Autodesk Inventor part; units mm, degrees
(part 2 of 2)
  spline S115 degree 3 poles (8.085, 6.6965) (8.085, 6.6966) (8.0755, 6.8111) (8.1685, 6.9061) (8.2142, 6.9788) knots 0.189655 0.189655 0.189655 0.189655 0.189655 0.206897 0.206897 0.206897 0.206897
  line L349 (8.085, 6.6965) -> (8.0755, 6.8111) construction
  line L350 (8.0755, 6.8111) -> (8.1685, 6.9061) construction
  line L351 (8.1685, 6.9061) -> (8.2142, 6.9788) construction
  spline S116 degree 3 poles (8.2142, 6.9788) (8.2143, 6.979) (8.3545, 7.2023) (8.3469, 7.2941) (8.4331, 7.5539) knots 0.206897 0.206897 0.206897 0.206897 0.206897 0.224138 0.224138 0.224138 0.224138
  line L352 (8.2142, 6.9788) -> (8.3545, 7.2023) construction
  line L353 (8.3545, 7.2023) -> (8.3469, 7.2941) construction
  line L354 (8.3469, 7.2941) -> (8.4331, 7.5539) construction
  spline S117 degree 3 poles (8.4331, 7.5539) (8.4331, 7.5541) (8.5076, 7.7786) (8.5783, 7.9124) (8.624, 8.1718) knots 0.224138 0.224138 0.224138 0.224138 0.224138 0.241379 0.241379 0.241379 0.241379
  line L355 (8.4331, 7.5539) -> (8.5076, 7.7786) construction
  line L356 (8.5076, 7.7786) -> (8.5783, 7.9124) construction
  line L357 (8.5783, 7.9124) -> (8.624, 8.1718) construction
  spline S118 degree 3 poles (8.624, 8.1718) (8.624, 8.172) (8.6663, 8.4124) (8.6795, 8.6592) (8.7001, 8.9071) knots 0.241379 0.241379 0.241379 0.241379 0.241379 0.258621 0.258621 0.258621 0.258621
  line L358 (8.624, 8.1718) -> (8.6663, 8.4124) construction
  line L359 (8.6663, 8.4124) -> (8.6795, 8.6592) construction
  line L360 (8.6795, 8.6592) -> (8.7001, 8.9071) construction
  spline S119 degree 3 poles (8.7001, 8.9071) (8.7001, 8.9073) (8.7102, 9.0279) (8.7321, 9.1622) (8.729, 9.2829) knots 0.258621 0.258621 0.258621 0.258621 0.258621 0.275862 0.275862 0.275862 0.275862
  line L361 (8.7001, 8.9071) -> (8.7102, 9.0279) construction
  line L362 (8.7102, 9.0279) -> (8.7321, 9.1622) construction
  line L363 (8.7321, 9.1622) -> (8.729, 9.2829) construction
  spline S120 degree 3 poles (8.729, 9.2829) (8.729, 9.283) (8.7263, 9.3865) (8.6763, 9.5788) (8.6969, 9.6501) knots 0.275862 0.275862 0.275862 0.275862 0.275862 0.293103 0.293103 0.293103 0.293103
  line L364 (8.729, 9.2829) -> (8.7263, 9.3865) construction
  line L365 (8.7263, 9.3865) -> (8.6763, 9.5788) construction
  line L366 (8.6763, 9.5788) -> (8.6969, 9.6501) construction
  spline S121 degree 3 poles (8.6969, 9.6501) (8.697, 9.6501) (8.8157, 9.6248) (8.819, 9.477) (8.9266, 9.3796) knots 0.293103 0.293103 0.293103 0.293103 0.293103 0.310345 0.310345 0.310345 0.310345
  line L367 (8.6969, 9.6501) -> (8.8157, 9.6248) construction
  line L368 (8.8157, 9.6248) -> (8.819, 9.477) construction
  line L369 (8.819, 9.477) -> (8.9266, 9.3796) construction
  spline S122 degree 3 poles (8.9266, 9.3796) (8.9268, 9.3797) (9.0711, 9.4527) (8.9677, 9.5952) (8.9205, 9.7051) knots 0.310345 0.310345 0.310345 0.310345 0.310345 0.327586 0.327586 0.327586 0.327586
  line L370 (8.9266, 9.3796) -> (9.0711, 9.4527) construction
  line L371 (9.0711, 9.4527) -> (8.9677, 9.5952) construction
  line L372 (8.9677, 9.5952) -> (8.9205, 9.7051) construction
  spline S123 degree 3 poles (8.9205, 9.7051) (8.9204, 9.7053) (8.8408, 9.891) (8.8788, 9.9473) (8.9212, 10.1294) knots 0.327586 0.327586 0.327586 0.327586 0.327586 0.344828 0.344828 0.344828 0.344828
  line L373 (8.9205, 9.7051) -> (8.8408, 9.891) construction
  line L374 (8.8408, 9.891) -> (8.8788, 9.9473) construction
  line L375 (8.8788, 9.9473) -> (8.9212, 10.1294) construction
  spline S124 degree 3 poles (8.9212, 10.1294) (8.9213, 10.1298) (9.0126, 10.5216) (8.7808, 10.9359) (8.5155, 11.2056) knots 0.344828 0.344828 0.344828 0.344828 0.344828 0.362069 0.362069 0.362069 0.362069
  line L376 (8.9212, 10.1294) -> (9.0126, 10.5216) construction
  line L377 (9.0126, 10.5216) -> (8.7808, 10.9359) construction
  line L378 (8.7808, 10.9359) -> (8.5155, 11.2056) construction
  spline S125 degree 3 poles (8.5155, 11.2056) (8.5153, 11.2057) (8.3918, 11.3312) (8.3839, 11.3395) (8.2897, 11.4877) knots 0.362069 0.362069 0.362069 0.362069 0.362069 0.37931 0.37931 0.37931 0.37931
  line L379 (8.5155, 11.2056) -> (8.3918, 11.3312) construction
  line L380 (8.3918, 11.3312) -> (8.3839, 11.3395) construction
  line L381 (8.3839, 11.3395) -> (8.2897, 11.4877) construction
  spline S126 degree 3 poles (8.2897, 11.4877) (8.2894, 11.488) (8.06, 11.8487) (8.0055, 11.7291) (7.6324, 11.6247) knots 0.37931 0.37931 0.37931 0.37931 0.37931 0.396552 0.396552 0.396552 0.396552
  line L382 (8.2897, 11.4877) -> (8.06, 11.8487) construction
  line L383 (8.06, 11.8487) -> (8.0055, 11.7291) construction
  line L384 (8.0055, 11.7291) -> (7.6324, 11.6247) construction
  spline S127 degree 3 poles (7.6324, 11.6247) (7.6324, 11.6247) (7.6491, 11.6371) (7.7644, 11.7585) (7.7775, 11.7819) knots 0.396552 0.396552 0.396552 0.396552 0.396552 0.413793 0.413793 0.413793 0.413793
  line L385 (7.6324, 11.6247) -> (7.6491, 11.6371) construction
  line L386 (7.6491, 11.6371) -> (7.7644, 11.7585) construction
  line L387 (7.7644, 11.7585) -> (7.7775, 11.7819) construction
  spline S128 degree 3 poles (7.7775, 11.7819) (7.7775, 11.7819) (7.8236, 11.8645) (7.7746, 11.9476) (7.7568, 12.0241) knots 0.413793 0.413793 0.413793 0.413793 0.413793 0.431034 0.431034 0.431034 0.431034
  line L388 (7.7775, 11.7819) -> (7.8236, 11.8645) construction
  line L389 (7.8236, 11.8645) -> (7.7746, 11.9476) construction
  line L390 (7.7746, 11.9476) -> (7.7568, 12.0241) construction
  spline S129 degree 3 poles (7.7568, 12.0241) (7.7571, 12.024) (8.0858, 11.859) (8.3087, 11.8206) (8.549, 12.0896) knots 0.431034 0.431034 0.431034 0.431034 0.431034 0.448276 0.448276 0.448276 0.448276
  line L391 (7.7568, 12.0241) -> (8.0858, 11.859) construction
  line L392 (8.0858, 11.859) -> (8.3087, 11.8206) construction
  line L393 (8.3087, 11.8206) -> (8.549, 12.0896) construction
  spline S130 degree 3 poles (8.549, 12.0896) (8.5492, 12.0898) (8.7512, 12.316) (8.8468, 12.4373) (8.9463, 12.8199) knots 0.448276 0.448276 0.448276 0.448276 0.448276 0.465517 0.465517 0.465517 0.465517
  line L394 (8.549, 12.0896) -> (8.7512, 12.316) construction
  line L395 (8.7512, 12.316) -> (8.8468, 12.4373) construction
  line L396 (8.8468, 12.4373) -> (8.9463, 12.8199) construction
  spline S131 degree 3 poles (8.9463, 12.8199) (8.9464, 12.8205) (9.0844, 13.3511) (9.2219, 14.254) (9.1072, 14.8125) knots 0.465517 0.465517 0.465517 0.465517 0.465517 0.482759 0.482759 0.482759 0.482759
  line L397 (8.9463, 12.8199) -> (9.0844, 13.3511) construction
  line L398 (9.0844, 13.3511) -> (9.2219, 14.254) construction
  line L399 (9.2219, 14.254) -> (9.1072, 14.8125) construction
  spline S132 degree 3 poles (9.1072, 14.8125) (9.1071, 14.8133) (8.9494, 15.581) (8.9114, 15.3471) (8.6266, 15.9994) knots 0.482759 0.482759 0.482759 0.482759 0.482759 0.5 0.5 0.5 0.5
  line L400 (9.1072, 14.8125) -> (8.9494, 15.581) construction
  line L401 (8.9494, 15.581) -> (8.9114, 15.3471) construction
  line L402 (8.9114, 15.3471) -> (8.6266, 15.9994) construction
  spline S133 degree 3 poles (8.6266, 15.9994) (8.6266, 15.9996) (8.5453, 16.1857) (8.0147, 16.2744) (7.8202, 16.319) knots 0.5 0.5 0.5 0.5 0.5 0.517241 0.517241 0.517241 0.517241
  line L403 (8.6266, 15.9994) -> (8.5453, 16.1857) construction
  line L404 (8.5453, 16.1857) -> (8.0147, 16.2744) construction
  line L405 (8.0147, 16.2744) -> (7.8202, 16.319) construction
  spline S134 degree 3 poles (7.8202, 16.319) (7.8197, 16.3191) (7.3838, 16.419) (7.4051, 16.0463) (7.2832, 15.7677) knots 0.517241 0.517241 0.517241 0.517241 0.517241 0.534483 0.534483 0.534483 0.534483
  line L406 (7.8202, 16.319) -> (7.3838, 16.419) construction
  line L407 (7.3838, 16.419) -> (7.4051, 16.0463) construction
  line L408 (7.4051, 16.0463) -> (7.2832, 15.7677) construction
  spline S135 degree 3 poles (7.2832, 15.7677) (7.2831, 15.7676) (7.228, 15.6417) (7.1184, 15.5346) (7.0933, 15.388) knots 0.534483 0.534483 0.534483 0.534483 0.534483 0.551724 0.551724 0.551724 0.551724
  line L409 (7.2832, 15.7677) -> (7.228, 15.6417) construction
  line L410 (7.228, 15.6417) -> (7.1184, 15.5346) construction
  line L411 (7.1184, 15.5346) -> (7.0933, 15.388) construction
  spline S136 degree 3 poles (7.0933, 15.388) (7.0933, 15.3879) (7.0679, 15.2397) (7.1046, 15.0222) (7.1143, 14.8711) knots 0.551724 0.551724 0.551724 0.551724 0.551724 0.568966 0.568966 0.568966 0.568966
  line L412 (7.0933, 15.388) -> (7.0679, 15.2397) construction
  line L413 (7.0679, 15.2397) -> (7.1046, 15.0222) construction
  line L414 (7.1046, 15.0222) -> (7.1143, 14.8711) construction
  spline S137 degree 3 poles (7.1143, 14.8711) (7.1143, 14.8709) (7.1285, 14.6518) (7.0596, 14.6036) (7.0137, 14.4186) knots 0.568966 0.568966 0.568966 0.568966 0.568966 0.586207 0.586207 0.586207 0.586207
  line L415 (7.1143, 14.8711) -> (7.1285, 14.6518) construction
  line L416 (7.1285, 14.6518) -> (7.0596, 14.6036) construction
  line L417 (7.0596, 14.6036) -> (7.0137, 14.4186) construction
  spline S138 degree 3 poles (7.0137, 14.4186) (7.0137, 14.4184) (6.9778, 14.2738) (6.9857, 13.9978) (6.9579, 13.9186) knots 0.586207 0.586207 0.586207 0.586207 0.586207 0.603448 0.603448 0.603448 0.603448
  line L418 (7.0137, 14.4186) -> (6.9778, 14.2738) construction
  line L419 (6.9778, 14.2738) -> (6.9857, 13.9978) construction
  line L420 (6.9857, 13.9978) -> (6.9579, 13.9186) construction
  spline S139 degree 3 poles (6.9579, 13.9186) (6.9579, 13.9186) (6.9279, 13.8333) (6.7142, 13.7453) (6.6278, 13.6772) knots 0.603448 0.603448 0.603448 0.603448 0.603448 0.62069 0.62069 0.62069 0.62069
  line L421 (6.9579, 13.9186) -> (6.9279, 13.8333) construction
  line L422 (6.9279, 13.8333) -> (6.7142, 13.7453) construction
  line L423 (6.7142, 13.7453) -> (6.6278, 13.6772) construction
  spline S140 degree 3 poles (6.6278, 13.6772) (6.6275, 13.677) (6.357, 13.4638) (6.3021, 13.3051) (5.9997, 13.1943) knots 0.62069 0.62069 0.62069 0.62069 0.62069 0.637931 0.637931 0.637931 0.637931
  line L424 (6.6278, 13.6772) -> (6.357, 13.4638) construction
  line L425 (6.357, 13.4638) -> (6.3021, 13.3051) construction
  line L426 (6.3021, 13.3051) -> (5.9997, 13.1943) construction
  spline S141 degree 3 poles (5.9997, 13.1943) (5.9994, 13.1942) (5.6348, 13.0606) (5.3959, 13.3366) (5.221, 13.4672) knots 0.637931 0.637931 0.637931 0.637931 0.637931 0.655172 0.655172 0.655172 0.655172
  line L427 (5.9997, 13.1943) -> (5.6348, 13.0606) construction
  line L428 (5.6348, 13.0606) -> (5.3959, 13.3366) construction
  line L429 (5.3959, 13.3366) -> (5.221, 13.4672) construction
  spline S142 degree 3 poles (5.221, 13.4672) (5.2206, 13.4675) (4.7972, 13.7836) (4.7334, 13.716) (4.4825, 13.552) knots 0.655172 0.655172 0.655172 0.655172 0.655172 0.672414 0.672414 0.672414 0.672414
  line L430 (5.221, 13.4672) -> (4.7972, 13.7836) construction
  line L431 (4.7972, 13.7836) -> (4.7334, 13.716) construction
  line L432 (4.7334, 13.716) -> (4.4825, 13.552) construction
  spline S143 degree 3 poles (4.4825, 13.552) (4.4824, 13.5519) (4.3251, 13.4491) (4.2622, 13.4755) (4.2786, 13.2069) knots 0.672414 0.672414 0.672414 0.672414 0.672414 0.689655 0.689655 0.689655 0.689655
  line L433 (4.4825, 13.552) -> (4.3251, 13.4491) construction
  line L434 (4.3251, 13.4491) -> (4.2622, 13.4755) construction
  line L435 (4.2622, 13.4755) -> (4.2786, 13.2069) construction
  spline S144 degree 3 poles (4.2786, 13.2069) (4.2786, 13.2067) (4.2897, 13.0241) (4.3834, 12.9269) (4.2992, 12.7362) knots 0.689655 0.689655 0.689655 0.689655 0.689655 0.706897 0.706897 0.706897 0.706897
  line L436 (4.2786, 13.2069) -> (4.2897, 13.0241) construction
  line L437 (4.2897, 13.0241) -> (4.3834, 12.9269) construction
  line L438 (4.3834, 12.9269) -> (4.2992, 12.7362) construction
  spline S145 degree 3 poles (4.2992, 12.7362) (4.2991, 12.736) (4.1856, 12.479) (4.0388, 12.1321) (4.2245, 11.8355) knots 0.706897 0.706897 0.706897 0.706897 0.706897 0.724138 0.724138 0.724138 0.724138
  line L439 (4.2992, 12.7362) -> (4.1856, 12.479) construction
  line L440 (4.1856, 12.479) -> (4.0388, 12.1321) construction
  line L441 (4.0388, 12.1321) -> (4.2245, 11.8355) construction
  spline S146 degree 3 poles (4.2245, 11.8355) (4.2245, 11.8354) (4.2873, 11.7351) (4.4143, 11.6294) (4.4987, 11.5541) knots 0.724138 0.724138 0.724138 0.724138 0.724138 0.741379 0.741379 0.741379 0.741379
  line L442 (4.2245, 11.8355) -> (4.2873, 11.7351) construction
  line L443 (4.2873, 11.7351) -> (4.4143, 11.6294) construction
  line L444 (4.4143, 11.6294) -> (4.4987, 11.5541) construction
  spline S147 degree 3 poles (4.4987, 11.5541) (4.4987, 11.5541) (4.541, 11.5164) (4.6082, 11.4653) (4.661, 11.4309) knots 0.741379 0.741379 0.741379 0.741379 0.741379 0.758621 0.758621 0.758621 0.758621
  line L445 (4.4987, 11.5541) -> (4.541, 11.5164) construction
  line L446 (4.541, 11.5164) -> (4.6082, 11.4653) construction
  line L447 (4.6082, 11.4653) -> (4.661, 11.4309) construction
  spline S148 degree 3 poles (4.661, 11.4309) (4.6611, 11.4308) (4.7908, 11.3461) (4.8176, 11.3664) (4.8049, 11.31) knots 0.758621 0.758621 0.758621 0.758621 0.758621 0.775862 0.775862 0.775862 0.775862
  line L448 (4.661, 11.4309) -> (4.7908, 11.3461) construction
  line L449 (4.7908, 11.3461) -> (4.8176, 11.3664) construction
  line L450 (4.8176, 11.3664) -> (4.8049, 11.31) construction
  spline S149 degree 3 poles (4.8049, 11.31) (4.8049, 11.31) (4.8017, 11.3093) (4.7933, 11.3094) (4.7952, 11.3096) knots 0.775862 0.775862 0.775862 0.775862 0.775862 0.793103 0.793103 0.793103 0.793103
  line L451 (4.8049, 11.31) -> (4.8017, 11.3093) construction
  line L452 (4.8017, 11.3093) -> (4.7933, 11.3094) construction
  line L453 (4.7933, 11.3094) -> (4.7952, 11.3096) construction
  line L454 (4.7952, 11.3096) -> (4.7557, 11.3178)
  spline S150 degree 3 poles (4.7557, 11.3178) (4.7554, 11.318) (4.4638, 11.4421) (4.1528, 11.8927) (3.9604, 11.9522) knots 0.810345 0.810345 0.810345 0.810345 0.810345 0.827586 0.827586 0.827586 0.827586
  line L455 (4.7557, 11.3178) -> (4.4638, 11.4421) construction
  line L456 (4.4638, 11.4421) -> (4.1528, 11.8927) construction
  line L457 (4.1528, 11.8927) -> (3.9604, 11.9522) construction
  spline S151 degree 3 poles (3.9604, 11.9522) (3.96, 11.9523) (3.59, 12.0667) (3.4363, 11.3591) (3.4025, 11.0291) knots 0.827586 0.827586 0.827586 0.827586 0.827586 0.844828 0.844828 0.844828 0.844828
  line L458 (3.9604, 11.9522) -> (3.59, 12.0667) construction
  line L459 (3.59, 12.0667) -> (3.4363, 11.3591) construction
  line L460 (3.4363, 11.3591) -> (3.4025, 11.0291) construction
  spline S152 degree 3 poles (3.4025, 11.0291) (3.4025, 11.0283) (3.3226, 10.2465) (3.593, 9.2162) (3.8261, 8.468) knots 0.844828 0.844828 0.844828 0.844828 0.844828 0.862069 0.862069 0.862069 0.862069
  line L461 (3.4025, 11.0291) -> (3.3226, 10.2465) construction
  line L462 (3.3226, 10.2465) -> (3.593, 9.2162) construction
  line L463 (3.593, 9.2162) -> (3.8261, 8.468) construction
  spline S153 degree 3 poles (3.8261, 8.468) (3.8263, 8.4672) (4.081, 7.6498) (4.3337, 6.9842) (4.7794, 6.4056) knots 0.862069 0.862069 0.862069 0.862069 0.862069 0.87931 0.87931 0.87931 0.87931
  line L464 (3.8261, 8.468) -> (4.081, 7.6498) construction
  line L465 (4.081, 7.6498) -> (4.3337, 6.9842) construction
  line L466 (4.3337, 6.9842) -> (4.7794, 6.4056) construction
  spline S154 degree 3 poles (4.7794, 6.4056) (4.7797, 6.4053) (5.0066, 6.1106) (5.2537, 5.8563) (5.7594, 6.1164) knots 0.87931 0.87931 0.87931 0.87931 0.87931 0.896552 0.896552 0.896552 0.896552
  line L467 (4.7794, 6.4056) -> (5.0066, 6.1106) construction
  line L468 (5.0066, 6.1106) -> (5.2537, 5.8563) construction
  line L469 (5.2537, 5.8563) -> (5.7594, 6.1164) construction
  spline S155 degree 3 poles (5.7594, 6.1164) (5.7596, 6.1164) (5.9091, 6.1933) (6.2195, 6.3788) (6.324, 6.4879) knots 0.896552 0.896552 0.896552 0.896552 0.896552 0.913793 0.913793 0.913793 0.913793
  line L470 (5.7594, 6.1164) -> (5.9091, 6.1933) construction
  line L471 (5.9091, 6.1933) -> (6.2195, 6.3788) construction
  line L472 (6.2195, 6.3788) -> (6.324, 6.4879) construction
  spline S156 degree 3 poles (6.324, 6.4879) (6.3241, 6.488) (6.3604, 6.526) (6.382, 6.5485) (6.4177, 6.5851) knots 0.913793 0.913793 0.913793 0.913793 0.913793 0.931034 0.931034 0.931034 0.931034
  line L473 (6.324, 6.4879) -> (6.3604, 6.526) construction
  line L474 (6.3604, 6.526) -> (6.382, 6.5485) construction
  line L475 (6.382, 6.5485) -> (6.4177, 6.5851) construction
  spline S157 degree 3 poles (6.4177, 6.5851) (6.4177, 6.5851) (6.4603, 6.6287) (6.4739, 6.6423) (6.5067, 6.6866) knots 0.931034 0.931034 0.931034 0.931034 0.931034 0.948276 0.948276 0.948276 0.948276
  line L476 (6.4177, 6.5851) -> (6.4603, 6.6287) construction
  line L477 (6.4603, 6.6287) -> (6.4739, 6.6423) construction
  line L478 (6.4739, 6.6423) -> (6.5067, 6.6866) construction
  spline S158 degree 3 poles (6.5067, 6.6866) (6.5067, 6.6866) (6.5211, 6.706) (6.5381, 6.7319) (6.5478, 6.7421) knots 0.948276 0.948276 0.948276 0.948276 0.948276 0.965517 0.965517 0.965517 0.965517
  line L479 (6.5067, 6.6866) -> (6.5211, 6.706) construction
  line L480 (6.5211, 6.706) -> (6.5381, 6.7319) construction
  line L481 (6.5381, 6.7319) -> (6.5478, 6.7421) construction
  spline S159 degree 3 poles (6.5478, 6.7421) (6.5478, 6.7421) (6.5873, 6.7836) (6.5397, 6.7821) (6.5939, 6.7607) knots 0.965517 0.965517 0.965517 0.965517 0.965517 1 1 1 1
  line L482 (6.5478, 6.7421) -> (6.5873, 6.7836) construction
  line L483 (6.5873, 6.7836) -> (6.5397, 6.7821) construction
  line L484 (6.5397, 6.7821) -> (6.5939, 6.7607) construction
  spline S160 degree 3 poles (4.2851, 13.5051) (4.4297, 13.5448) (4.5345, 13.6609) (4.6648, 13.7189) knots 0 0 0 0 0.019231 0.019231 0.019231 0.019231
  line L485 (4.2851, 13.5051) -> (4.4297, 13.5448) construction
  line L486 (4.4297, 13.5448) -> (4.5345, 13.6609) construction
  line L487 (4.5345, 13.6609) -> (4.6648, 13.7189) construction
  spline S161 degree 3 poles (4.6648, 13.7189) (4.665, 13.7189) (4.7945, 13.7765) (4.7214, 13.7105) (4.8252, 13.8605) knots 0.019231 0.019231 0.019231 0.019231 0.019231 0.038462 0.038462 0.038462 0.038462
  line L488 (4.6648, 13.7189) -> (4.7945, 13.7765) construction
  line L489 (4.7945, 13.7765) -> (4.7214, 13.7105) construction
  line L490 (4.7214, 13.7105) -> (4.8252, 13.8605) construction
  spline S162 degree 3 poles (4.8252, 13.8605) (4.8252, 13.8605) (4.8679, 13.9221) (4.9144, 13.9823) (4.9623, 14.0252) knots 0.038462 0.038462 0.038462 0.038462 0.038462 0.057692 0.057692 0.057692 0.057692
  line L491 (4.8252, 13.8605) -> (4.8679, 13.9221) construction
  line L492 (4.8679, 13.9221) -> (4.9144, 13.9823) construction
  line L493 (4.9144, 13.9823) -> (4.9623, 14.0252) construction
  spline S163 degree 3 poles (4.9623, 14.0252) (4.9625, 14.0253) (5.0874, 14.1374) (5.1887, 14.1581) (5.3951, 14.1947) knots 0.057692 0.057692 0.057692 0.057692 0.057692 0.076923 0.076923 0.076923 0.076923
  line L494 (4.9623, 14.0252) -> (5.0874, 14.1374) construction
  line L495 (5.0874, 14.1374) -> (5.1887, 14.1581) construction
  line L496 (5.1887, 14.1581) -> (5.3951, 14.1947) construction
  spline S164 degree 3 poles (5.3951, 14.1947) (5.3952, 14.1947) (5.4953, 14.2124) (5.8415, 14.2782) (5.9178, 14.2358) knots 0.076923 0.076923 0.076923 0.076923 0.076923 0.096154 0.096154 0.096154 0.096154
  line L497 (5.3951, 14.1947) -> (5.4953, 14.2124) construction
  line L498 (5.4953, 14.2124) -> (5.8415, 14.2782) construction
  line L499 (5.8415, 14.2782) -> (5.9178, 14.2358) construction
  spline S165 degree 3 poles (5.9178, 14.2358) (5.9178, 14.2358) (5.8459, 14.1688) (5.2071, 14.2272) (4.9664, 13.9892) knots 0.096154 0.096154 0.096154 0.096154 0.096154 0.115385 0.115385 0.115385 0.115385
  line L500 (5.9178, 14.2358) -> (5.8459, 14.1688) construction
  line L501 (5.8459, 14.1688) -> (5.2071, 14.2272) construction
  line L502 (5.2071, 14.2272) -> (4.9664, 13.9892) construction
  spline S166 degree 3 poles (4.9664, 13.9892) (4.9664, 13.9891) (4.9233, 13.9465) (4.8213, 13.8146) (4.7924, 13.7378) knots 0.115385 0.115385 0.115385 0.115385 0.115385 0.134615 0.134615 0.134615 0.134615
  line L503 (4.9664, 13.9892) -> (4.9233, 13.9465) construction
  line L504 (4.9233, 13.9465) -> (4.8213, 13.8146) construction
  line L505 (4.8213, 13.8146) -> (4.7924, 13.7378) construction
  spline S167 degree 3 poles (4.7924, 13.7378) (4.7926, 13.7378) (4.9422, 13.7123) (5.1457, 13.585) (5.2643, 13.4944) knots 0.134615 0.134615 0.134615 0.134615 0.134615 0.153846 0.153846 0.153846 0.153846
  line L506 (4.7924, 13.7378) -> (4.9422, 13.7123) construction
  line L507 (4.9422, 13.7123) -> (5.1457, 13.585) construction
  line L508 (5.1457, 13.585) -> (5.2643, 13.4944) construction
  spline S168 degree 3 poles (5.2643, 13.4944) (5.2644, 13.4944) (5.3197, 13.4522) (5.3424, 13.4244) (5.4024, 13.3854) knots 0.153846 0.153846 0.153846 0.153846 0.153846 0.173077 0.173077 0.173077 0.173077
  line L509 (5.2643, 13.4944) -> (5.3197, 13.4522) construction
  line L510 (5.3197, 13.4522) -> (5.3424, 13.4244) construction
  line L511 (5.3424, 13.4244) -> (5.4024, 13.3854) construction
  spline S169 degree 3 poles (5.4024, 13.3854) (5.4025, 13.3854) (5.4803, 13.4032) (5.5294, 13.4409) (5.568, 13.4828) knots 0.173077 0.173077 0.173077 0.173077 0.173077 0.192308 0.192308 0.192308 0.192308
  line L512 (5.4024, 13.3854) -> (5.4803, 13.4032) construction
  line L513 (5.4803, 13.4032) -> (5.5294, 13.4409) construction
  line L514 (5.5294, 13.4409) -> (5.568, 13.4828) construction
  spline S170 degree 3 poles (5.568, 13.4828) (5.5683, 13.4831) (5.8625, 13.8033) (5.7592, 13.6299) (5.9471, 13.7705) knots 0.192308 0.192308 0.192308 0.192308 0.192308 0.211538 0.211538 0.211538 0.211538
  line L515 (5.568, 13.4828) -> (5.8625, 13.8033) construction
  line L516 (5.8625, 13.8033) -> (5.7592, 13.6299) construction
  line L517 (5.7592, 13.6299) -> (5.9471, 13.7705) construction
  spline S171 degree 3 poles (5.9471, 13.7705) (5.9471, 13.7706) (6.006, 13.8147) (5.9676, 13.8137) (6.0399, 13.8289) knots 0.211538 0.211538 0.211538 0.211538 0.211538 0.230769 0.230769 0.230769 0.230769
  line L518 (5.9471, 13.7705) -> (6.006, 13.8147) construction
  line L519 (6.006, 13.8147) -> (5.9676, 13.8137) construction
  line L520 (5.9676, 13.8137) -> (6.0399, 13.8289) construction
  spline S172 degree 3 poles (6.0399, 13.8289) (6.0399, 13.8288) (5.9915, 13.7123) (5.8366, 13.7047) (5.7267, 13.6103) knots 0.230769 0.230769 0.230769 0.230769 0.230769 0.25 0.25 0.25 0.25
  line L521 (6.0399, 13.8289) -> (5.9915, 13.7123) construction
  line L522 (5.9915, 13.7123) -> (5.8366, 13.7047) construction
  line L523 (5.8366, 13.7047) -> (5.7267, 13.6103) construction
  spline S173 degree 3 poles (5.7267, 13.6103) (5.7266, 13.6102) (5.6212, 13.5196) (5.5939, 13.4227) (5.4357, 13.3596) knots 0.25 0.25 0.25 0.25 0.25 0.269231 0.269231 0.269231 0.269231
  line L524 (5.7267, 13.6103) -> (5.6212, 13.5196) construction
  line L525 (5.6212, 13.5196) -> (5.5939, 13.4227) construction
  line L526 (5.5939, 13.4227) -> (5.4357, 13.3596) construction
  spline S174 degree 3 poles (5.4357, 13.3596) (5.4359, 13.3594) (5.6329, 13.175) (5.8696, 13.1641) (6.1237, 13.3077) knots 0.269231 0.269231 0.269231 0.269231 0.269231 0.288462 0.288462 0.288462 0.288462
  line L527 (5.4357, 13.3596) -> (5.6329, 13.175) construction
  line L528 (5.6329, 13.175) -> (5.8696, 13.1641) construction
  line L529 (5.8696, 13.1641) -> (6.1237, 13.3077) construction
  spline S175 degree 3 poles (6.1237, 13.3077) (6.1238, 13.3078) (6.2514, 13.3799) (6.2941, 13.4307) (6.3861, 13.5223) knots 0.288462 0.288462 0.288462 0.288462 0.288462 0.307692 0.307692 0.307692 0.307692
  line L530 (6.1237, 13.3077) -> (6.2514, 13.3799) construction
  line L531 (6.2514, 13.3799) -> (6.2941, 13.4307) construction
  line L532 (6.2941, 13.4307) -> (6.3861, 13.5223) construction
  spline S176 degree 3 poles (6.3861, 13.5223) (6.3862, 13.5225) (6.541, 13.6768) (6.4055, 13.7495) (6.4135, 13.8704) knots 0.307692 0.307692 0.307692 0.307692 0.307692 0.326923 0.326923 0.326923 0.326923
  line L533 (6.3861, 13.5223) -> (6.541, 13.6768) construction
  line L534 (6.541, 13.6768) -> (6.4055, 13.7495) construction
  line L535 (6.4055, 13.7495) -> (6.4135, 13.8704) construction
  line L536 (6.4135, 13.8704) -> (6.4184, 13.8927)
  spline S177 degree 3 poles (6.4184, 13.8927) (6.4184, 13.8927) (6.4596, 13.8412) (6.4858, 13.721) (6.4896, 13.6527) knots 0.346154 0.346154 0.346154 0.346154 0.346154 0.365385 0.365385 0.365385 0.365385
  line L537 (6.4184, 13.8927) -> (6.4596, 13.8412) construction
  line L538 (6.4596, 13.8412) -> (6.4858, 13.721) construction
  line L539 (6.4858, 13.721) -> (6.4896, 13.6527) construction
  spline S178 degree 3 poles (6.4896, 13.6527) (6.4898, 13.653) (6.7259, 13.9155) (6.5878, 14.0223) (6.5455, 14.1088) knots 0.365385 0.365385 0.365385 0.365385 0.365385 0.384615 0.384615 0.384615 0.384615
  line L540 (6.4896, 13.6527) -> (6.7259, 13.9155) construction
  line L541 (6.7259, 13.9155) -> (6.5878, 14.0223) construction
  line L542 (6.5878, 14.0223) -> (6.5455, 14.1088) construction
  spline S179 degree 3 poles (6.5455, 14.1088) (6.5456, 14.1089) (6.6464, 14.1857) (6.7022, 14.1917) (6.781, 14.2823) knots 0.384615 0.384615 0.384615 0.384615 0.384615 0.403846 0.403846 0.403846 0.403846
  line L543 (6.5455, 14.1088) -> (6.6464, 14.1857) construction
  line L544 (6.6464, 14.1857) -> (6.7022, 14.1917) construction
  line L545 (6.7022, 14.1917) -> (6.781, 14.2823) construction
  spline S180 degree 3 poles (6.781, 14.2823) (6.7809, 14.2823) (6.6717, 14.2841) (6.5286, 14.2648) (6.4365, 14.3152) knots 0.403846 0.403846 0.403846 0.403846 0.403846 0.423077 0.423077 0.423077 0.423077
  line L546 (6.781, 14.2823) -> (6.6717, 14.2841) construction
  line L547 (6.6717, 14.2841) -> (6.5286, 14.2648) construction
  line L548 (6.5286, 14.2648) -> (6.4365, 14.3152) construction
  spline S181 degree 3 poles (6.4365, 14.3152) (6.4365, 14.3152) (6.4648, 14.3382) (6.4618, 14.332) (6.5466, 14.3205) knots 0.423077 0.423077 0.423077 0.423077 0.423077 0.442308 0.442308 0.442308 0.442308
  line L549 (6.4365, 14.3152) -> (6.4648, 14.3382) construction
  line L550 (6.4648, 14.3382) -> (6.4618, 14.332) construction
  line L551 (6.4618, 14.332) -> (6.5466, 14.3205) construction
  spline S182 degree 3 poles (6.5466, 14.3205) (6.5468, 14.3205) (6.7559, 14.292) (6.8283, 14.3075) (6.9094, 14.4277) knots 0.442308 0.442308 0.442308 0.442308 0.442308 0.461538 0.461538 0.461538 0.461538
  line L552 (6.5466, 14.3205) -> (6.7559, 14.292) construction
  line L553 (6.7559, 14.292) -> (6.8283, 14.3075) construction
  line L554 (6.8283, 14.3075) -> (6.9094, 14.4277) construction
  spline S183 degree 3 poles (6.9094, 14.4277) (6.9095, 14.4278) (7.0128, 14.5808) (7.1945, 15.1025) (6.5991, 14.8175) knots 0.461538 0.461538 0.461538 0.461538 0.461538 0.480769 0.480769 0.480769 0.480769
  line L555 (6.9094, 14.4277) -> (7.0128, 14.5808) construction
  line L556 (7.0128, 14.5808) -> (7.1945, 15.1025) construction
  line L557 (7.1945, 15.1025) -> (6.5991, 14.8175) construction
  spline S184 degree 3 poles (6.5991, 14.8175) (6.5989, 14.8174) (6.412, 14.7279) (6.441, 14.6341) (6.3626, 14.6248) knots 0.480769 0.480769 0.480769 0.480769 0.480769 0.5 0.5 0.5 0.5
  line L558 (6.5991, 14.8175) -> (6.412, 14.7279) construction
  line L559 (6.412, 14.7279) -> (6.441, 14.6341) construction
  line L560 (6.441, 14.6341) -> (6.3626, 14.6248) construction
  spline S185 degree 3 poles (6.3626, 14.6248) (6.3626, 14.6248) (6.3713, 14.688) (6.5046, 14.8084) (6.5733, 14.8423) knots 0.5 0.5 0.5 0.5 0.5 0.519231 0.519231 0.519231 0.519231
  line L561 (6.3626, 14.6248) -> (6.3713, 14.688) construction
  line L562 (6.3713, 14.688) -> (6.5046, 14.8084) construction
  line L563 (6.5046, 14.8084) -> (6.5733, 14.8423) construction
  spline S186 degree 3 poles (6.5733, 14.8423) (6.5734, 14.8424) (6.6972, 14.9035) (6.7744, 14.917) (6.9254, 14.9369) knots 0.519231 0.519231 0.519231 0.519231 0.519231 0.538462 0.538462 0.538462 0.538462
  line L564 (6.5733, 14.8423) -> (6.6972, 14.9035) construction
  line L565 (6.6972, 14.9035) -> (6.7744, 14.917) construction
  line L566 (6.7744, 14.917) -> (6.9254, 14.9369) construction
  spline S187 degree 3 poles (6.9254, 14.9369) (6.9256, 14.9369) (7.1756, 14.9698) (6.9074, 15.2407) (7.1453, 15.6201) knots 0.538462 0.538462 0.538462 0.538462 0.538462 0.557692 0.557692 0.557692 0.557692
  line L567 (6.9254, 14.9369) -> (7.1756, 14.9698) construction
  line L568 (7.1756, 14.9698) -> (6.9074, 15.2407) construction
  line L569 (6.9074, 15.2407) -> (7.1453, 15.6201) construction
  spline S188 degree 3 poles (7.1453, 15.6201) (7.1453, 15.6202) (7.1842, 15.6823) (7.2842, 15.833) (7.2627, 15.9217) knots 0.557692 0.557692 0.557692 0.557692 0.557692 0.576923 0.576923 0.576923 0.576923
  line L570 (7.1453, 15.6201) -> (7.1842, 15.6823) construction
  line L571 (7.1842, 15.6823) -> (7.2842, 15.833) construction
  line L572 (7.2842, 15.833) -> (7.2627, 15.9217) construction
  spline S189 degree 3 poles (7.2627, 15.9217) (7.2626, 15.9221) (7.1708, 16.3021) (6.3817, 16.1044) (6.2657, 15.998) knots 0.576923 0.576923 0.576923 0.576923 0.576923 0.596154 0.596154 0.596154 0.596154
  line L573 (7.2627, 15.9217) -> (7.1708, 16.3021) construction
  line L574 (7.1708, 16.3021) -> (6.3817, 16.1044) construction
  line L575 (6.3817, 16.1044) -> (6.2657, 15.998) construction
  spline S190 degree 3 poles (6.2657, 15.998) (6.2658, 15.9978) (6.3592, 15.8678) (6.4213, 15.7841) (6.3614, 15.5624) knots 0.596154 0.596154 0.596154 0.596154 0.596154 0.615385 0.615385 0.615385 0.615385
  line L576 (6.2657, 15.998) -> (6.3592, 15.8678) construction
  line L577 (6.3592, 15.8678) -> (6.4213, 15.7841) construction
  line L578 (6.4213, 15.7841) -> (6.3614, 15.5624) construction
  spline S191 degree 3 poles (6.3614, 15.5624) (6.3614, 15.5623) (6.3224, 15.4179) (6.2356, 15.2302) (6.127, 15.1822) knots 0.615385 0.615385 0.615385 0.615385 0.615385 0.634615 0.634615 0.634615 0.634615
  line L579 (6.3614, 15.5624) -> (6.3224, 15.4179) construction
  line L580 (6.3224, 15.4179) -> (6.2356, 15.2302) construction
  line L581 (6.2356, 15.2302) -> (6.127, 15.1822) construction
  spline S192 degree 3 poles (6.127, 15.1822) (6.127, 15.1823) (6.146, 15.2304) (6.4781, 15.6017) (6.3055, 15.8851) knots 0.634615 0.634615 0.634615 0.634615 0.634615 0.653846 0.653846 0.653846 0.653846
  line L582 (6.127, 15.1822) -> (6.146, 15.2304) construction
  line L583 (6.146, 15.2304) -> (6.4781, 15.6017) construction
  line L584 (6.4781, 15.6017) -> (6.3055, 15.8851) construction
  spline S193 degree 3 poles (6.3055, 15.8851) (6.3054, 15.8852) (6.2296, 16.0099) (6.1501, 16.0291) (5.9292, 15.9932) knots 0.653846 0.653846 0.653846 0.653846 0.653846 0.673077 0.673077 0.673077 0.673077
  line L585 (6.3055, 15.8851) -> (6.2296, 16.0099) construction
  line L586 (6.2296, 16.0099) -> (6.1501, 16.0291) construction
  line L587 (6.1501, 16.0291) -> (5.9292, 15.9932) construction
  spline S194 degree 3 poles (5.9292, 15.9932) (5.929, 15.9932) (5.7464, 15.9635) (5.7048, 15.885) (5.5876, 15.8427) knots 0.673077 0.673077 0.673077 0.673077 0.673077 0.692308 0.692308 0.692308 0.692308
  line L588 (5.9292, 15.9932) -> (5.7464, 15.9635) construction
  line L589 (5.7464, 15.9635) -> (5.7048, 15.885) construction
  line L590 (5.7048, 15.885) -> (5.5876, 15.8427) construction
  spline S195 degree 3 poles (5.5876, 15.8427) (5.5876, 15.8426) (5.6071, 15.7057) (5.6162, 15.6776) (5.6011, 15.5294) knots 0.692308 0.692308 0.692308 0.692308 0.692308 0.711538 0.711538 0.711538 0.711538
  line L591 (5.5876, 15.8427) -> (5.6071, 15.7057) construction
  line L592 (5.6071, 15.7057) -> (5.6162, 15.6776) construction
  line L593 (5.6162, 15.6776) -> (5.6011, 15.5294) construction
  spline S196 degree 3 poles (5.6011, 15.5294) (5.6011, 15.5292) (5.582, 15.3413) (5.6535, 15.3796) (5.6897, 15.2779) knots 0.711538 0.711538 0.711538 0.711538 0.711538 0.730769 0.730769 0.730769 0.730769
  line L594 (5.6011, 15.5294) -> (5.582, 15.3413) construction
  line L595 (5.582, 15.3413) -> (5.6535, 15.3796) construction
  line L596 (5.6535, 15.3796) -> (5.6897, 15.2779) construction
  spline S197 degree 3 poles (5.6897, 15.2779) (5.6895, 15.2779) (5.4765, 15.3474) (5.6227, 15.6216) (5.5528, 15.815) knots 0.730769 0.730769 0.730769 0.730769 0.730769 0.75 0.75 0.75 0.75
  line L597 (5.6897, 15.2779) -> (5.4765, 15.3474) construction
  line L598 (5.4765, 15.3474) -> (5.6227, 15.6216) construction
  line L599 (5.6227, 15.6216) -> (5.5528, 15.815) construction
  spline S198 degree 3 poles (5.5528, 15.815) (5.5526, 15.815) (5.3008, 15.843) (5.0826, 15.6258) (5.017, 15.4582) knots 0.75 0.75 0.75 0.75 0.75 0.769231 0.769231 0.769231 0.769231
  line L600 (5.5528, 15.815) -> (5.3008, 15.843) construction
  line L601 (5.3008, 15.843) -> (5.0826, 15.6258) construction
  line L602 (5.0826, 15.6258) -> (5.017, 15.4582) construction
  spline S199 degree 3 poles (5.017, 15.4582) (5.0171, 15.4581) (5.0943, 15.3712) (5.1592, 15.3665) (5.184, 15.2971) knots 0.769231 0.769231 0.769231 0.769231 0.769231 0.788462 0.788462 0.788462 0.788462
  line L603 (5.017, 15.4582) -> (5.0943, 15.3712) construction
  line L604 (5.0943, 15.3712) -> (5.1592, 15.3665) construction
  line L605 (5.1592, 15.3665) -> (5.184, 15.2971) construction
  spline S200 degree 3 poles (5.184, 15.2971) (5.1839, 15.2972) (5.0925, 15.3276) (5.061, 15.3877) (4.9897, 15.4276) knots 0.788462 0.788462 0.788462 0.788462 0.788462 0.807692 0.807692 0.807692 0.807692
  line L606 (5.184, 15.2971) -> (5.0925, 15.3276) construction
  line L607 (5.0925, 15.3276) -> (5.061, 15.3877) construction
  line L608 (5.061, 15.3877) -> (4.9897, 15.4276) construction
  spline S201 degree 3 poles (4.9897, 15.4276) (4.9893, 15.4275) (4.6443, 15.3223) (4.3627, 14.794) (4.4142, 14.6118) knots 0.807692 0.807692 0.807692 0.807692 0.807692 0.826923 0.826923 0.826923 0.826923
  line L609 (4.9897, 15.4276) -> (4.6443, 15.3223) construction
  line L610 (4.6443, 15.3223) -> (4.3627, 14.794) construction
  line L611 (4.3627, 14.794) -> (4.4142, 14.6118) construction
  spline S202 degree 3 poles (4.4142, 14.6118) (4.4144, 14.6118) (4.5519, 14.5436) (4.6705, 14.5794) (4.7787, 14.6531) knots 0.826923 0.826923 0.826923 0.826923 0.826923 0.846154 0.846154 0.846154 0.846154
  line L612 (4.4142, 14.6118) -> (4.5519, 14.5436) construction
  line L613 (4.5519, 14.5436) -> (4.6705, 14.5794) construction
  line L614 (4.6705, 14.5794) -> (4.7787, 14.6531) construction
  spline S203 degree 3 poles (4.7787, 14.6531) (4.7788, 14.6532) (4.8831, 14.7243) (4.9502, 14.7625) (5.0988, 14.7944) knots 0.846154 0.846154 0.846154 0.846154 0.846154 0.865385 0.865385 0.865385 0.865385
  line L615 (4.7787, 14.6531) -> (4.8831, 14.7243) construction
  line L616 (4.8831, 14.7243) -> (4.9502, 14.7625) construction
  line L617 (4.9502, 14.7625) -> (5.0988, 14.7944) construction
  spline S204 degree 3 poles (5.0988, 14.7944) (5.099, 14.7945) (5.2332, 14.8233) (5.3816, 14.8359) (5.5222, 14.814) knots 0.865385 0.865385 0.865385 0.865385 0.865385 0.884615 0.884615 0.884615 0.884615
  line L618 (5.0988, 14.7944) -> (5.2332, 14.8233) construction
  line L619 (5.2332, 14.8233) -> (5.3816, 14.8359) construction
  line L620 (5.3816, 14.8359) -> (5.5222, 14.814) construction
  spline S205 degree 3 poles (5.5222, 14.814) (5.5223, 14.814) (5.6178, 14.799) (5.6893, 14.7741) (5.7698, 14.731) knots 0.884615 0.884615 0.884615 0.884615 0.884615 0.903846 0.903846 0.903846 0.903846
  line L621 (5.5222, 14.814) -> (5.6178, 14.799) construction
  line L622 (5.6178, 14.799) -> (5.6893, 14.7741) construction
  line L623 (5.6893, 14.7741) -> (5.7698, 14.731) construction
  spline S206 degree 3 poles (5.7698, 14.731) (5.7698, 14.731) (5.8247, 14.7015) (5.8194, 14.7114) (5.8366, 14.6605) knots 0.903846 0.903846 0.903846 0.903846 0.903846 0.923077 0.923077 0.923077 0.923077
  line L624 (5.7698, 14.731) -> (5.8247, 14.7015) construction
  line L625 (5.8247, 14.7015) -> (5.8194, 14.7114) construction
  line L626 (5.8194, 14.7114) -> (5.8366, 14.6605) construction
  spline S207 degree 3 poles (5.8366, 14.6605) (5.8364, 14.6606) (5.605, 14.7492) (5.5145, 14.858) (5.0725, 14.7567) knots 0.923077 0.923077 0.923077 0.923077 0.923077 0.942308 0.942308 0.942308 0.942308
  line L627 (5.8366, 14.6605) -> (5.605, 14.7492) construction
  line L628 (5.605, 14.7492) -> (5.5145, 14.858) construction
  line L629 (5.5145, 14.858) -> (5.0725, 14.7567) construction
  spline S208 degree 3 poles (5.0725, 14.7567) (5.0722, 14.7566) (4.7566, 14.6844) (4.7781, 14.476) (4.3848, 14.5828) knots 0.942308 0.942308 0.942308 0.942308 0.942308 0.961538 0.961538 0.961538 0.961538
  line L630 (5.0725, 14.7567) -> (4.7566, 14.6844) construction
  line L631 (4.7566, 14.6844) -> (4.7781, 14.476) construction
  line L632 (4.7781, 14.476) -> (4.3848, 14.5828) construction
  spline S209 degree 3 poles (4.3848, 14.5828) (4.3846, 14.5825) (4.1945, 14.2894) (4.0202, 13.8259) (4.2851, 13.5051) knots 0.961538 0.961538 0.961538 0.961538 0.961538 1 1 1 1
  line L633 (4.3848, 14.5828) -> (4.1945, 14.2894) construction
  line L634 (4.1945, 14.2894) -> (4.0202, 13.8259) construction
  line L635 (4.0202, 13.8259) -> (4.2851, 13.5051) construction
  point P0 (0, 12)
  constraints: 206 coincident, 12 end point, 630 other
equation "\"d134\" = 0.5 * d133"
equation "\"d135\" = 0.5 * d132"
equation "\"d141\" = 0.5 * d140"
equation "\"d142\" = 0.5 * d136"
body "Solid1"
